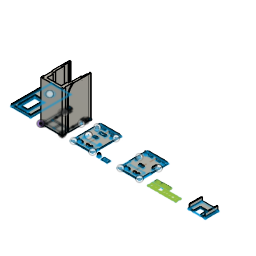
no_DICE-Enclosure-v18 (Autodesk Fusion 360 design; units mm, degrees)
part number: 2026-08-05-22-37-30-025
Autodesk Fusion 360 part; units mm, degrees
(part 1 of 2)
sketch "Frame" plane through (0, 0, 0) normal (0, 1, 0) x (1, 0, 0)
  line L0 (0, 0) -> (4, 0)
  line L1 (4, 0) -> (4, 42)
  line L2 (4, 42) -> (0, 42)
  line L3 (0, 42) -> (0, 0)
  line L4 (4, 39) -> (4, 42)
  line L5 (0, 0) -> (32, 0)
  line L6 (32, 0) -> (32, 3.8)
  line L7 (32, 3.8) -> (0, 3.8)
  line L8 (0, 3.8) -> (0, 0)
  line L9 (4, 13) -> (28, 13)
  line L10 (28, 13) -> (28, 15)
  line L11 (28, 15) -> (4, 15)
  line L12 (4, 15) -> (4, 13)
  line L13 (4, 18) -> (3.2, 18)
  line L14 (3.2, 18) -> (3.2, 20)
  line L15 (3.2, 20) -> (4, 20)
  line L16 (4, 20) -> (4, 18)
  line L17 (4, 39) -> (7, 39)
  line L18 (7, 39) -> (7, 35)
  line L19 (7, 35) -> (4, 35)
  line L20 (4, 35) -> (4, 39)
  line L21 (4, 42) -> (1, 42)
  line L22 (1, 42) -> (1, 39)
  line L23 (1, 39) -> (4, 39)
  line L24 (4, 39) -> (4, 42)
  line L25 (4, 3.8) -> (5.5, 3.8)
  line L26 (5.5, 3.8) -> (5.5, 13)
  line L27 (5.5, 13) -> (4, 13)
  line L28 (4, 13) -> (4, 3.8)
  line L29 (3.2, 20) -> (4, 20)
  line L30 (4, 20) -> (4, 35)
  line L31 (4, 35) -> (3.2, 35)
  line L32 (3.2, 35) -> (3.2, 20)
  line L33 (32, 0) -> (28, 0)
  line L34 (28, 0) -> (28, 42)
  line L35 (28, 42) -> (32, 42)
  line L36 (32, 42) -> (32, 0)
  line L37 (28, 18) -> (28.8, 18)
  line L38 (28.8, 18) -> (28.8, 20)
  line L39 (28.8, 20) -> (28, 20)
  line L40 (28, 20) -> (28, 18)
  line L41 (28, 39) -> (31, 39)
  line L42 (31, 39) -> (31, 42)
  line L43 (31, 42) -> (28, 42)
  line L44 (28, 42) -> (28, 39)
  line L45 (28, 39) -> (25, 39)
  line L46 (25, 39) -> (25, 35)
  line L47 (25, 35) -> (28, 35)
  line L48 (28, 35) -> (28, 39)
  line L49 (28.8, 20) -> (28, 20)
  line L50 (28, 20) -> (28, 35)
  line L51 (28, 35) -> (28.8, 35)
  line L52 (28.8, 35) -> (28.8, 20)
  line L53 (28, 3.8) -> (26.5, 3.8)
  line L54 (26.5, 3.8) -> (26.5, 13)
  line L55 (26.5, 13) -> (28, 13)
  line L56 (28, 13) -> (28, 3.8)
  line L57 (7, 36) -> (2, 36)
  line L58 (2, 36) -> (2, 37.4)
  line L59 (2, 37.4) -> (7, 37.4)
  line L60 (7, 37.4) -> (7, 36)
  line L61 (25, 36) -> (30, 36)
  line L62 (30, 36) -> (30, 37.4)
  line L63 (30, 37.4) -> (25, 37.4)
  line L64 (25, 37.4) -> (25, 36)
  line L65 (15, 13) -> (17, 13)
  line L66 (17, 13) -> (17, 3.8)
  line L67 (17, 3.8) -> (15, 3.8)
  line L68 (15, 3.8) -> (15, 13)
  line L69 (2, 37.4) -> (2, 39)
  line L70 (30, 37.4) -> (30, 39)
  line L71 (2, 36) -> (2, 32)
  line L72 (2, 32) -> (4, 32)
  line L73 (30, 36) -> (30, 32)
  line L74 (30, 32) -> (28, 32)
  line L75 (0, 42) -> (1, 42)
  line L76 (1, 42) -> (1, 42.1)
  line L77 (1, 42.1) -> (0, 42.1)
  line L78 (0, 42.1) -> (0, 42)
  line L79 (0, 42.1) -> (2, 42.1)
  line L80 (2, 42.1) -> (2, 43.1)
  line L81 (2, 43.1) -> (0, 43.1)
  line L82 (0, 43.1) -> (0, 42.1)
  line L83 (32, 42) -> (31, 42)
  line L84 (31, 42) -> (31, 42.1)
  line L85 (31, 42.1) -> (32, 42.1)
  line L86 (32, 42.1) -> (32, 42)
  line L87 (32, 42.1) -> (30, 42.1)
  line L88 (30, 42.1) -> (30, 43.1)
  line L89 (30, 43.1) -> (32, 43.1)
  line L90 (32, 43.1) -> (32, 42.1)
  circle A0 centre (1.6, 30) radius 0.65
  circle A1 centre (30.4, 30) radius 0.65
  circle A2 centre (2, 2) radius 0.65
  circle A3 centre (30, 2) radius 0.65
  circle A4 centre (2, 37) radius 0.65
  circle A5 centre (30, 37) radius 0.65
  dimension "d1" = 4
  dimension "d2" = 42
  dimension "d4" = 32
  dimension "d5" = 3.8
  dimension "d6" = 24
  dimension "d7" = 2
  dimension "d8" = 0.8
  dimension "d9" = 2
  dimension "d10" = 3
  dimension "d11" = 4
  dimension "d12" = 9.2
  dimension "d13" = 3
  dimension "d14" = 3
  dimension "d15" = 3
  dimension "d16" = 1.5
  dimension "d17" = 4
  dimension "d18" = 42
  dimension "d19" = 0.8
  dimension "d20" = 2
  dimension "d21" = 3
  dimension "d22" = 3
  dimension "d23" = 3
  dimension "d24" = 3
  dimension "d25" = 4
  dimension "d26" = 1.5
  dimension "d27" = 9.2
  dimension "d43" = 3
  dimension "d44" = 5
  dimension "d45" = 1.4
  dimension "d46" = 5
  dimension "d47" = 1.4
  dimension "d52" = 1
  dimension "d53" = 1
  dimension "d133" = 2
  dimension "d134" = 15
  dimension "d164" = 4
  dimension "d165" = 4
  dimension "d174" = 0.1
  dimension "d175" = 2
  dimension "d176" = 1
  dimension "d177" = 0.1
  dimension "d178" = 2
  dimension "d179" = 1
  dimension "d428" = 1.3
  dimension "d429" = 1.6
  dimension "d430" = 2
  dimension "d431" = 1.3
  dimension "d432" = 1.6
  dimension "d433" = 2
  dimension "d434" = 1.3
  dimension "d435" = 2
  dimension "d436" = 2
  dimension "d437" = 1.3
  dimension "d438" = 2
  dimension "d439" = 2
  dimension "d458" = 1.3
  dimension "d459" = 2
  dimension "d460" = 6.1
  dimension "d461" = 1.3
  dimension "d462" = 2
  dimension "d463" = 6.1
  constraint horizontal L0
  constraint vertical L1
  constraint horizontal L2
  constraint vertical L3
  constraint coincident L0.start L3.end
  constraint vertical L4
  constraint horizontal L5
  constraint vertical L6
  constraint horizontal L7
  constraint vertical L8
  constraint horizontal L9
  constraint vertical L10
  constraint horizontal L11
  constraint vertical L12
  constraint coincident L1 L9.start
  constraint horizontal L13
  constraint vertical L14
  constraint horizontal L15
  constraint vertical L16
  constraint coincident L1 L13.start
  constraint horizontal L17
  constraint vertical L18
  constraint horizontal L19
  constraint vertical L20
  constraint horizontal L21
  constraint vertical L22
  constraint horizontal L23
  constraint vertical L24
  constraint horizontal L25
  constraint vertical L26
  constraint horizontal L27
  constraint vertical L28
  constraint coincident L7 L25.start
  constraint coincident L1 L25.start
  constraint horizontal L29
  constraint vertical L30
  constraint horizontal L31
  constraint vertical L32
  constraint horizontal L33
  constraint vertical L34
  constraint horizontal L35
  constraint vertical L36
  constraint horizontal L37
  constraint vertical L38
  constraint horizontal L39
  constraint vertical L40
  constraint coincident L34 L37.start
  constraint horizontal L41
  constraint vertical L42
  constraint horizontal L43
  constraint vertical L44
  constraint coincident L34 L41.start
  constraint horizontal L45
  constraint vertical L46
  constraint horizontal L47
  constraint vertical L48
  constraint horizontal L49
  constraint vertical L50
  constraint horizontal L51
  constraint vertical L52
  constraint horizontal L53
  constraint vertical L54
  constraint horizontal L55
  constraint vertical L56
  constraint coincident L7 L53.start
  constraint coincident L34 L53.start
  constraint collinear L35 L43
  constraint horizontal L57
  constraint vertical L58
  constraint horizontal L59
  constraint vertical L60
  constraint coincident L18 L57.start
  constraint horizontal L61
  constraint vertical L62
  constraint horizontal L63
  constraint vertical L64
  constraint coincident L46 L61.start
  constraint horizontal L65
  constraint vertical L66
  constraint horizontal L67
  constraint vertical L68
  constraint coincident L9 L65.start
  constraint coincident L23 L69.end
  constraint perpendicular L23 L69
  constraint coincident L41 L70.end
  constraint perpendicular L41 L70
  constraint perpendicular L57 L71
  constraint perpendicular L32 L72
  constraint perpendicular L61 L73
  constraint coincident L50 L74.end
  constraint horizontal L75
  constraint vertical L76
  constraint horizontal L77
  constraint vertical L78
  constraint horizontal L79
  constraint vertical L80
  constraint horizontal L81
  constraint vertical L82
  constraint horizontal L83
  constraint vertical L84
  constraint horizontal L85
  constraint vertical L86
  constraint horizontal L87
  constraint vertical L88
  constraint horizontal L89
  constraint vertical L90
  measures "d1" distance of L0.start L0.end
  measures "d2" distance of L0.start L2.end
  measures "d4" distance of L0.start L5.end
  measures "d5" distance of L0.start L7.end
  measures "d6" distance of L9.start L9.end
  measures "d7" distance of L9.start L11.end
  measures "d8" distance of L13.start L13.end
  measures "d9" distance of L13.start L15.end
  measures "d10" distance of L4.start L17.end
  measures "d11" distance of L4.start L19.end
  measures "d12" distance of L7 L9
  measures "d13" distance of L11 L13
  measures "d14" distance of L1.end L21.end
  measures "d15" distance of L1.end L4.start
  measures "d16" distance of L25.start L25.end
  measures "d17" distance of L5.end L33.end
  measures "d18" distance of L5.end L35.end
  measures "d19" distance of L37.start L37.end
  measures "d20" distance of L37.start L39.end
  measures "d21" distance of L11 L37
  measures "d22" distance of L41.start L41.end
  measures "d23" distance of L41.start L34.end
  measures "d24" distance of L41.start L45.end
  measures "d25" distance of L41.start L47.end
  measures "d26" distance of L53.start L53.end
  measures "d27" distance of L53.start L9.end
  measures "d43" distance of L2 L17
  measures "d44" distance of L57.start L57.end
  measures "d45" distance of L57.start L59.end
  measures "d46" distance of L61.start L61.end
  measures "d47" distance of L61.start L63.end
  measures "d52" distance of L19 L57
  measures "d53" distance of L47 L61
  measures "d133" distance of L65.start L65.end
  measures "d134" distance of L3 L68
  measures "d164" distance of L57.end L71.end
  measures "d165" distance of L61.end L73.end
  measures "d174" distance of L2.end L77.end
  measures "d175" distance of L77.end L79.end
  measures "d176" distance of L77.end L81.end
  measures "d177" distance of L35.end L85.end
  measures "d178" distance of L85.end L87.end
  measures "d179" distance of L85.end L89.end
  measures "d428" diameter of A0
  measures "d429" distance of L3 A0.centre
  measures "d430" distance of L72 A0.centre
  measures "d431" diameter of A1
  measures "d432" distance of L36 A1.centre
  measures "d433" distance of L74 A1.centre
  measures "d434" diameter of A2
  measures "d435" distance of L0 A2.centre
  measures "d436" distance of L3 A2.centre
  measures "d437" diameter of A3
  measures "d438" distance of L5 A3.centre
  measures "d439" distance of L6 A3.centre
  measures "d458" diameter of A4
  measures "d459" distance of L3 A4.centre
  measures "d460" distance of L81 A4.centre
  measures "d461" diameter of A5
  measures "d462" distance of L36 A5.centre
  measures "d463" distance of L89 A5.centre
extrude "Extrude4" add sketch "Frame" along normal blind 10 contours L0 L1 L3 L5 L7 L8 | L1 L5 L7 L25 L34 L53 L67 | L1 L2 L3 L7 L12 L13 L14 L22 L23 L28 L32 L58 L69 L71 L72 L75 A4 | L1 L7 L9 L25 L26 L27 L28 | L5 L6 L7 L33 L34 L36 | L7 L10 L34 L35 L36 L37 L38 L41 L42 L52 L56 L62 L70 L73 L74 L83 A5 | L7 L9 L34 L53 L54 L55 L56 | L1 L20 L23 L59 L69 A4 | L1 L20 L57 L58 L59 A4 | L59 L69 A4 | L58 L69 A4 | L1 L20 L31 L32 L57 L71 L72 | L58 L59 A4 | L34 L41 L48 L63 L70 A5 | L34 L48 L51 L52 L61 L73 L74 | L34 L48 L61 L62 L63 A5 | L62 L70 A5 | L63 L70 A5 | L62 L63 A5 | A0 | A1 | A2 | A3 makes body 1
extrude "Extrude5" add sketch "Frame" along normal blind 10 contours L1 L15 L29 L30 L32 L72 | L1 L30 L31 L32 L72 | L34 L39 L49 L50 L52 L74 | L34 L50 L51 L52 L74 bodies 1
extrude "Extrude6" add sketch "Frame" along normal blind 10 contours L1 L9 L10 L11 L12 L27 L34 L55 L65 bodies 1
extrude "Extrude7" add sketch "Frame" along normal blind 10 contours L1 L17 L18 L20 L59 | L1 L18 L20 L57 L59 L60 | L1 L18 L19 L20 L57 | L34 L45 L46 L48 L63 | L34 L46 L47 L48 L61 | L34 L46 L48 L61 L63 L64 bodies 1
extrude "Extrude8" cut sketch "Frame" along normal blind 10 contours L1 L18 L20 L57 L59 L60 | L1 L20 L57 L58 L59 A4 | L58 L59 A4 | L34 L48 L61 L62 L63 A5 | L34 L46 L48 L61 L63 L64 | L62 L63 A5 bodies 1
extrude "Extrude9" add sketch "Frame" along normal blind 5 contours L1 L18 L20 L57 L59 L60 | L1 L20 L57 L58 L59 A4 | L58 L59 A4 | L34 L48 L61 L62 L63 A5 | L34 L46 L48 L61 L63 L64 | L62 L63 A5 bodies 1
sketch "Side IO" plane through (0, 0, 0) normal (0, 1, 0) x (1, 0, 0)
  line L0 (45, 0.0196) -> (77, 0.0196)
  line L1 (77, 0.0196) -> (77, 43.1196)
  line L2 (77, 43.1196) -> (45, 43.1196)
  line L3 (45, 43.1196) -> (45, 0.0196)
  circle A0 centre (47, 2.0196) radius 1.1
  circle A1 centre (75, 2.0196) radius 1.1
  circle A2 centre (47, 37.0196) radius 1.1
  circle A3 centre (75, 37.0196) radius 1.1
  line L4 (50.6, 4.0196) -> (71.4, 4.0196)
  line L5 (71.4, 4.0196) -> (71.4, 13.0196)
  line L6 (71.4, 13.0196) -> (50.6, 13.0196)
  line L7 (50.6, 13.0196) -> (50.6, 4.0196)
  line L8 (49.1, 15.0196) -> (51.1, 15.0196)
  line L9 (51.1, 15.0196) -> (51.1, 17.0196)
  line L10 (51.1, 17.0196) -> (49.1, 17.0196)
  line L11 (49.1, 17.0196) -> (49.1, 15.0196)
  line L12 (51.1, 17.0196) -> (50.1, 17.0196)
  line L13 (50.1, 17.0196) -> (50.1, 16.0196)
  line L14 (50.1, 16.0196) -> (51.1, 16.0196)
  line L15 (51.1, 16.0196) -> (51.1, 17.0196)
  line L16 (72.9, 15.0196) -> (70.9, 15.0196)
  line L17 (70.9, 15.0196) -> (70.9, 17.0196)
  line L18 (70.9, 17.0196) -> (72.9, 17.0196)
  line L19 (72.9, 17.0196) -> (72.9, 15.0196)
  line L20 (70.9, 17.0196) -> (71.9, 17.0196)
  line L21 (71.9, 17.0196) -> (71.9, 16.0196)
  line L22 (71.9, 16.0196) -> (70.9, 16.0196)
  line L23 (70.9, 16.0196) -> (70.9, 17.0196)
  line L24 (49.1, 34.7196) -> (51.1, 34.7196)
  line L25 (51.1, 34.7196) -> (51.1, 32.7196)
  line L26 (51.1, 32.7196) -> (49.1, 32.7196)
  line L27 (49.1, 32.7196) -> (49.1, 34.7196)
  line L28 (51.1, 32.7196) -> (50.1, 32.7196)
  line L29 (50.1, 32.7196) -> (50.1, 33.7196)
  line L30 (50.1, 33.7196) -> (51.1, 33.7196)
  line L31 (51.1, 33.7196) -> (51.1, 32.7196)
  line L32 (70.9, 32.7196) -> (72.9, 32.7196)
  line L33 (72.9, 32.7196) -> (72.9, 34.7196)
  line L34 (72.9, 34.7196) -> (70.9, 34.7196)
  line L35 (70.9, 34.7196) -> (70.9, 32.7196)
  line L36 (70.9, 32.7196) -> (71.9, 32.7196)
  line L37 (71.9, 32.7196) -> (71.9, 33.7196)
  line L38 (71.9, 33.7196) -> (70.9, 33.7196)
  line L39 (70.9, 33.7196) -> (70.9, 32.7196)
  line L40 (56.5, 23.8196) -> (62.5, 23.8196)
  line L41 (62.5, 23.8196) -> (62.5, 20.6196)
  line L42 (62.5, 20.6196) -> (56.5, 20.6196)
  line L43 (56.5, 20.6196) -> (56.5, 23.8196)
  line L44 (56.2, 33.2196) -> (65.8, 33.2196)
  line L45 (65.8, 33.2196) -> (65.8, 29.8196)
  line L46 (65.8, 29.8196) -> (56.2, 29.8196)
  line L47 (56.2, 29.8196) -> (56.2, 33.2196)
  line L48 (50.6, 4.0196) -> (52.6, 4.0196)
  line L49 (52.6, 4.0196) -> (52.6, 6.0196)
  line L50 (52.6, 6.0196) -> (50.6, 6.0196)
  line L51 (50.6, 6.0196) -> (50.6, 4.0196)
  line L52 (52.6, 6.0196) -> (51.6, 6.0196)
  line L53 (51.6, 6.0196) -> (51.6, 5.0196)
  line L54 (51.6, 5.0196) -> (52.6, 5.0196)
  line L55 (52.6, 5.0196) -> (52.6, 6.0196)
  line L56 (71.4, 4.0196) -> (69.4, 4.0196)
  line L57 (69.4, 4.0196) -> (69.4, 6.0196)
  line L58 (69.4, 6.0196) -> (71.4, 6.0196)
  line L59 (71.4, 6.0196) -> (71.4, 4.0196)
  line L60 (69.4, 6.0196) -> (70.4, 6.0196)
  line L61 (70.4, 6.0196) -> (70.4, 5.0196)
  line L62 (70.4, 5.0196) -> (69.4, 5.0196)
  line L63 (69.4, 5.0196) -> (69.4, 6.0196)
  line L64 (54, 4.0196) -> (58, 4.0196)
  line L65 (58, 4.0196) -> (58, 5.0196)
  line L66 (58, 5.0196) -> (54, 5.0196)
  line L67 (54, 5.0196) -> (54, 4.0196)
  line L68 (61, 4.0196) -> (61, 13.0196) construction
  line L69 (64, 4.0196) -> (68, 4.0196)
  line L70 (68, 4.0196) -> (68, 5.0196)
  line L71 (68, 5.0196) -> (64, 5.0196)
  line L72 (64, 5.0196) -> (64, 4.0196)
  line L73 (46.8, 43.1196) -> (75.2, 43.1196)
  line L74 (75.2, 43.1196) -> (75.2, 42.1196)
  line L75 (75.2, 42.1196) -> (46.8, 42.1196)
  line L76 (46.8, 42.1196) -> (46.8, 43.1196)
  line L77 (61, 13.0196) -> (61, 42.1196) construction
  line L78 (58, 39.1196) -> (52, 39.1196)
  line L79 (52, 39.1196) -> (52, 38.1196)
  line L80 (52, 38.1196) -> (58, 38.1196)
  line L81 (58, 38.1196) -> (58, 39.1196)
  line L82 (64, 39.1196) -> (70, 39.1196)
  line L83 (70, 39.1196) -> (70, 38.1196)
  line L84 (70, 38.1196) -> (64, 38.1196)
  line L85 (64, 38.1196) -> (64, 39.1196)
  line L86 (45, 5.0196) -> (46, 5.0196)
  line L87 (46, 5.0196) -> (46, 9.0196)
  line L88 (46, 9.0196) -> (45, 9.0196)
  line L89 (45, 9.0196) -> (45, 5.0196)
  line L90 (77, 5.0196) -> (76, 5.0196)
  line L91 (76, 5.0196) -> (76, 9.0196)
  line L92 (76, 9.0196) -> (77, 9.0196)
  line L93 (77, 9.0196) -> (77, 5.0196)
  circle A4 centre (50.8, 20.2196) radius 0.4
  dimension "d54" = 32
  dimension "d55" = 43.1
  dimension "d56" = 2.2
  dimension "d57" = 2
  dimension "d58" = 2
  dimension "d59" = 2.2
  dimension "d60" = 2
  dimension "d61" = 2
  dimension "d62" = 2.2
  dimension "d63" = 6.1
  dimension "d64" = 2
  dimension "d65" = 2.2
  dimension "d66" = 6.1
  dimension "d67" = 2
  dimension "d68" = 20.8
  dimension "d69" = 9
  dimension "d70" = 4
  dimension "d71" = 5.6
  dimension "d73" = 2
  dimension "d74" = 2
  dimension "d75" = 4.1
  dimension "d76" = 2
  dimension "d77" = 2
  dimension "d78" = 2
  dimension "d79" = 2
  dimension "d80" = 4.1
  dimension "d81" = 2
  dimension "d82" = 2
  dimension "d83" = 4.1
  dimension "d84" = 8.4
  dimension "d85" = 2
  dimension "d86" = 2
  dimension "d87" = 4.1
  dimension "d88" = 8.4
  dimension "d89" = 6
  dimension "d90" = 3.2
  dimension "d91" = 20.6
  dimension "d93" = 11.5
  dimension "d94" = 9.6
  dimension "d95" = 3.4
  dimension "d96" = 11.2
  dimension "d109" = 2
  dimension "d110" = 2
  dimension "d111" = 1
  dimension "d112" = 1
  dimension "d113" = 2
  dimension "d114" = 2
  dimension "d115" = 1
  dimension "d116" = 1
  dimension "d121" = 1
  dimension "d122" = 1
  dimension "d123" = 1
  dimension "d124" = 1
  dimension "d125" = 1
  dimension "d126" = 1
  dimension "d127" = 1
  dimension "d128" = 1
  dimension "d182" = 4
  dimension "d183" = 1
  dimension "d184" = 3
  dimension "d185" = 4
  dimension "d186" = 1
  dimension "d187" = 3
  dimension "d192" = 29.8
  dimension "d193" = 28.4
  dimension "d194" = 1
  dimension "d195" = 1.8
  dimension "d345" = 6
  dimension "d346" = 1
  dimension "d347" = 3
  dimension "d348" = 4
  dimension "d349" = 6
  dimension "d350" = 1
  dimension "d351" = 3
  dimension "d352" = 4
  dimension "d372" = 1
  dimension "d373" = 4
  dimension "d374" = 5
  dimension "d375" = 1
  dimension "d376" = 4
  dimension "d377" = 5
  dimension "d423" = 0.8
  dimension "d424" = 20.2
  dimension "d425" = 5.8
  constraint horizontal L0
  constraint vertical L1
  constraint horizontal L2
  constraint vertical L3
  constraint horizontal L4
  constraint vertical L5
  constraint horizontal L6
  constraint vertical L7
  constraint horizontal L8
  constraint vertical L9
  constraint horizontal L10
  constraint vertical L11
  constraint horizontal L12
  constraint vertical L13
  constraint horizontal L14
  constraint vertical L15
  constraint horizontal L16
  constraint vertical L17
  constraint horizontal L18
  constraint vertical L19
  constraint horizontal L20
  constraint vertical L21
  constraint horizontal L22
  constraint vertical L23
  constraint horizontal L24
  constraint vertical L25
  constraint horizontal L26
  constraint vertical L27
  constraint horizontal L28
  constraint vertical L29
  constraint horizontal L30
  constraint vertical L31
  constraint horizontal L32
  constraint vertical L33
  constraint horizontal L34
  constraint vertical L35
  constraint horizontal L36
  constraint vertical L37
  constraint horizontal L38
  constraint vertical L39
  constraint horizontal L40
  constraint vertical L41
  constraint horizontal L42
  constraint vertical L43
  constraint horizontal L44
  constraint vertical L45
  constraint horizontal L46
  constraint vertical L47
  constraint horizontal L48
  constraint vertical L49
  constraint horizontal L50
  constraint vertical L51
  constraint horizontal L52
  constraint vertical L53
  constraint horizontal L54
  constraint vertical L55
  constraint horizontal L56
  constraint vertical L57
  constraint horizontal L58
  constraint vertical L59
  constraint horizontal L60
  constraint vertical L61
  constraint horizontal L62
  constraint vertical L63
  constraint horizontal L64
  constraint vertical L65
  constraint horizontal L66
  constraint vertical L67
  constraint coincident L4 L64.start
  constraint midpoint L4 L68.start
  constraint midpoint L6 L68.end
  constraint horizontal L69
  constraint vertical L70
  constraint horizontal L71
  constraint vertical L72
  constraint coincident L4 L69.start
  constraint horizontal L73
  constraint vertical L74
  constraint horizontal L75
  constraint vertical L76
  constraint coincident L2 L73.start
  constraint midpoint L75 L77.end
  constraint horizontal L78
  constraint vertical L79
  constraint horizontal L80
  constraint vertical L81
  constraint horizontal L82
  constraint vertical L83
  constraint horizontal L84
  constraint vertical L85
  constraint horizontal L86
  constraint vertical L87
  constraint horizontal L88
  constraint vertical L89
  constraint coincident L3 L86.start
  constraint horizontal L90
  constraint vertical L91
  constraint horizontal L92
  constraint vertical L93
  constraint coincident L1 L90.start
  measures "d54" distance of L0.start L0.end
  measures "d55" distance of L0.start L2.end
  measures "d56" diameter of A0
  measures "d57" distance of L0 A0.centre
  measures "d58" distance of L3 A0.centre
  measures "d59" diameter of A1
  measures "d60" distance of L0 A1.centre
  measures "d61" distance of L1 A1.centre
  measures "d62" diameter of A2
  measures "d63" distance of L2 A2.centre
  measures "d64" distance of L3 A2.centre
  measures "d65" diameter of A3
  measures "d66" distance of L2 A3.centre
  measures "d67" distance of L1 A3.centre
  measures "d68" distance of L4.start L4.end
  measures "d69" distance of L4.start L6.end
  measures "d70" distance of L0 L4
  measures "d71" distance of L3 L7
  measures "d73" distance of L8.start L8.end
  measures "d74" distance of L8.start L10.end
  measures "d75" distance of L3 L11
  measures "d76" distance of L6 L8
  measures "d77" distance of L16.start L16.end
  measures "d78" distance of L16.start L18.end
  measures "d79" distance of L6 L16
  measures "d80" distance of L1 L19
  measures "d81" distance of L24.start L24.end
  measures "d82" distance of L24.start L26.end
  measures "d83" distance of L3 L27
  measures "d84" distance of L2 L24
  measures "d85" distance of L32.start L32.end
  measures "d86" distance of L32.start L34.end
  measures "d87" distance of L1 L33
  measures "d88" distance of L2 L34
  measures "d89" distance of L40.start L40.end
  measures "d90" distance of L40.start L42.end
  measures "d91" distance of L0 L42
  measures "d93" distance of L3 L43
  measures "d94" distance of L44.start L44.end
  measures "d95" distance of L44.start L46.end
  measures "d96" distance of L3 L47
  measures "d109" distance of L4.start L48.end
  measures "d110" distance of L4.start L50.end
  measures "d111" distance of L49.end L52.end
  measures "d112" distance of L49.end L54.end
  measures "d113" distance of L4.end L56.end
  measures "d114" distance of L4.end L58.end
  measures "d115" distance of L57.end L60.end
  measures "d116" distance of L57.end L62.end
  measures "d121" distance of L11 L13
  measures "d122" distance of L8 L14
  measures "d123" distance of L16 L22
  measures "d124" distance of L19 L21
  measures "d125" distance of L34 L38
  measures "d126" distance of L33 L37
  measures "d127" distance of L24 L30
  measures "d128" distance of L27 L29
  measures "d182" distance of L64.start L64.end
  measures "d183" distance of L64.start L66.end
  measures "d184" distance of L65 L68
  measures "d185" distance of L69.start L69.end
  measures "d186" distance of L69.start L71.end
  measures "d187" distance of L68 L72
  measures "d192" distance of L0 L46
  measures "d193" distance of L73.start L73.end
  measures "d194" distance of L73.start L75.end
  measures "d195" distance of L3 L76
  measures "d345" distance of L78.start L78.end
  measures "d346" distance of L78.start L80.end
  measures "d347" distance of L77 L81
  measures "d348" distance of L2 L78
  measures "d349" distance of L82.start L82.end
  measures "d350" distance of L82.start L84.end
  measures "d351" distance of L77 L85
  measures "d352" distance of L2 L82
  measures "d372" distance of L86.start L86.end
  measures "d373" distance of L86.start L88.end
  measures "d374" distance of L0 L86
  measures "d375" distance of L90.start L90.end
  measures "d376" distance of L90.start L92.end
  measures "d377" distance of L0 L90
  measures "d423" diameter of A4
  measures "d424" distance of L0 A4.centre
  measures "d425" distance of L3 A4.centre
extrude "Extrude10" add sketch "Side IO" along normal blind 1 separate body contours L0 L1 L2 L3 L74 L75 L76 L86 L87 L88 L90 L91 L92 | L3 L86 L87 L88 L89 | L1 L90 L91 L92 L93 | L2 L73 L74 L75 L76 | L9 L10 L12 L13 L14 L15 | L17 L18 L20 L21 L22 L23 | L25 L26 L28 L29 L30 L31 | L32 L35 L36 L37 L38 L39 | L78 L79 L80 L81 | L82 L83 L84 L85 | A4 makes body 2
extrude "Extrude11" add sketch "Side IO" along normal blind 1 contours L4 L7 L48 L49 L50 L51 L53 L54 | L4 L5 L6 L7 L49 L50 L52 L55 L57 L58 L60 L63 L65 L66 L67 L70 L71 L72 | L4 L64 L65 L66 L67 | L49 L50 L52 L53 L54 L55 | L4 L69 L70 L71 L72 | L4 L5 L56 L57 L58 L59 L61 L62 | L57 L58 L60 L61 L62 L63 | L8 L9 L10 L11 L13 L14 | L16 L17 L18 L19 L21 L22 | L24 L25 L26 L27 L29 L30 | L32 L33 L34 L35 L37 L38 bodies 2
sketch "Switch Handle (exp)" plane through (0, 0, 0) normal (0, 1, 0) x (1, 0, 0)
  line L0 (85, 0) -> (86.9, 0)
  line L1 (86.9, 0) -> (86.9, 1.9)
  line L2 (86.9, 1.9) -> (85, 1.9)
  line L3 (85, 1.9) -> (85, 0)
  line L4 (84.6, -0.4) -> (87.3, -0.4)
  line L5 (87.3, -0.4) -> (87.3, 2.3)
  line L6 (87.3, 2.3) -> (84.6, 2.3)
  line L7 (84.6, 2.3) -> (84.6, -0.4)
  dimension "d102" = 1.9
  dimension "d103" = 1.9
  dimension "d104" = 0.4
  constraint horizontal L0
  constraint vertical L1
  constraint horizontal L2
  constraint vertical L3
  measures "d102" distance of L0.start L0.end
  measures "d103" distance of L0.start L2.end
extrude "Extrude12" add sketch "Switch Handle (exp)" along normal blind 4 separate body makes body 3
extrude "Extrude13" add sketch "Switch Handle (exp)" along normal blind 1 contours L0 L1 L2 L3 bodies 3
extrude "Extrude14" add sketch "Side IO" along normal blind 4 contours L4 L7 L48 L49 L50 L51 L53 L54 | L4 L5 L56 L57 L58 L59 L61 L62 | L24 L25 L26 L27 L29 L30 | L32 L33 L34 L35 L37 L38 bodies 2
fillet "Fillet1" radius 1 4 edges at (56.2, 0.5, -33.2196) (65.8, 0.5, -33.2196) (65.8, 0.5, -29.8196) (56.2, 0.5, -29.8196) on bodies 2
fillet "Fillet2" radius 1 4 edges at (56.5, 0.5, -23.8196) (62.5, 0.5, -23.8196) (62.5, 0.5, -20.6196) (56.5, 0.5, -20.6196) on bodies 2
extrude "Extrude15" add sketch "Frame" along normal blind 0.6 contours L1 L13 L14 L15 L16 L29 | L34 L37 L38 L39 L40 L49 bodies 1
extrude "Extrude16" add sketch "Frame" along normal blind 1 contours L7 L9 L65 L66 L67 L68 bodies 1
sketch "Top" plane through (0, 0, 0) normal (0, 1, 0) x (1, 0, 0)
  line L0 (-15, 0) -> (-44.2, 0)
  line L1 (-44.2, 0) -> (-44.2, 59.8)
  line L2 (-44.2, 59.8) -> (-15, 59.8)
  line L3 (-15, 59.8) -> (-15, 0)
  line L4 (-25, 5.8) -> (-37.8, 5.8)
  line L5 (-37.8, 5.8) -> (-37.8, 29)
  line L6 (-37.8, 29) -> (-25, 29)
  line L7 (-25, 29) -> (-25, 5.8)
  circle A0 centre (-31.4, 44.8) radius 3.6
  line L8 (-16, 58.8) -> (-16, 1)
  line L9 (-16, 1) -> (-43.2, 1)
  line L10 (-43.2, 1) -> (-43.2, 58.8)
  line L11 (-43.2, 58.8) -> (-16, 58.8)
  line L12 (-25.4, 6.2) -> (-37.4, 6.2)
  line L13 (-37.4, 6.2) -> (-37.4, 28.6)
  line L14 (-37.4, 28.6) -> (-25.4, 28.6)
  line L15 (-25.4, 28.6) -> (-25.4, 6.2)
  circle A1 centre (-31.4, 44.8) radius 5.6
  line L16 (-24, 30) -> (-24, 4.8)
  line L17 (-24, 4.8) -> (-38.8, 4.8)
  line L18 (-38.8, 4.8) -> (-38.8, 30)
  line L19 (-38.8, 30) -> (-24, 30)
  dimension "d137" = 29.2
  dimension "d138" = 59.8
  dimension "d139" = 12.8
  dimension "d140" = 23.2
  dimension "d141" = 5.8
  dimension "d143" = 7.2
  dimension "d144" = 12.8
  dimension "d145" = 15
  dimension "d146" = 1
  dimension "d147" = 0.4
  dimension "d148" = 2
  dimension "d151" = -1
  dimension "d358" = 6.4
  constraint horizontal L0
  constraint vertical L1
  constraint horizontal L2
  constraint vertical L3
  constraint horizontal L4
  constraint vertical L5
  constraint horizontal L6
  constraint vertical L7
  measures "d137" distance of L0.start L0.end
  measures "d138" distance of L0.start L2.end
  measures "d139" distance of L4.start L4.end
  measures "d140" distance of L4.start L6.end
  measures "d141" distance of L0 L4
  measures "d143" diameter of A0
  measures "d144" distance of L1 A0.centre
  measures "d145" distance of L2 A0.centre
  measures "d358" distance of L1 L5
extrude "Extrude19" add sketch "Top" along normal blind 1 separate body contours L0 L1 L2 L3 | L8 L9 L10 L11 | A1 | L16 L17 L18 L19 makes body 4
extrude "Extrude20" add sketch "Top" along normal blind 3 contours L0 L1 L2 L3 | A1 | L16 L17 L18 L19 bodies 4
extrude "Extrude21" add sketch "Top" along normal blind 0.8 contours L4 L5 L6 L7 bodies 4
fillet "Fillet3" radius 1 4 edges at (-16, 2, -58.8) (-16, 2, -1) (-43.2, 2, -1) (-43.2, 2, -58.8) on bodies 4
extrude "Extrude23" add sketch "Frame" along normal blind 22 contours L0 L1 L3 L5 L7 L8 | L1 L5 L7 L25 L34 L53 L67 | L1 L2 L3 L7 L12 L13 L14 L22 L23 L28 L32 L58 L69 L71 L72 L75 A4 | L1 L7 L9 L25 L26 L27 L28 | L5 L6 L7 L33 L34 L36 | L1 L9 L10 L11 L12 L27 L34 L55 L65 | L7 L10 L34 L35 L36 L37 L38 L41 L42 L52 L56 L62 L70 L73 L74 L83 A5 | L7 L9 L34 L53 L54 L55 L56 | L1 L15 L29 L30 L32 L72 | L58 L69 A4 | L34 L39 L49 L50 L52 L74 | L62 L70 A5 | A0 | A1 | A2 | A3 bodies 1
extrude "Extrude25" add sketch "Frame" along normal blind 60 contours L0 L1 L3 L5 L7 L8 | L1 L5 L7 L25 L34 L53 L67 | L1 L2 L3 L7 L12 L13 L14 L22 L23 L28 L32 L58 L69 L71 L72 L75 A4 | L1 L7 L9 L25 L26 L27 L28 | L5 L6 L7 L33 L34 L36 | L7 L10 L34 L35 L36 L37 L38 L41 L42 L52 L56 L62 L70 L73 L74 L83 A5 | L7 L9 L34 L53 L54 L55 L56 | L58 L69 A4 | L62 L70 A5 | A0 | A1 | A2 | A3 bodies 1
extrude "Extrude26" add sketch "Frame" along normal blind 60 contours L2 L75 L76 L77 L78 L79 | L77 L79 L80 L81 L82 | L35 L83 L84 L85 L86 L87 | L85 L87 L88 L89 L90 bodies 1
extrude "Extrude27" add sketch "Side IO" along normal blind 4 contours L4 L64 L65 L66 L67 | L4 L69 L70 L71 L72 bodies 2
fillet "Fillet4" radius 0.4 2 edges at (56, 1, -5.0196) (66, 1, -5.0196) on bodies 2
extrude "Extrude28" add sketch "Side IO" along normal blind 2 contours L2 L73 L74 L75 L76 bodies 2
fillet "Fillet5" radius 0.4 4 edges at (77, 0.5, -0.0196) (45, 0.5, -0.0196) (77, 0.5, -43.1196) (45, 0.5, -43.1196) on bodies 2
sketch "Switch Skirt" plane through (0, 0, 0) normal (0, 1, 0) x (1, 0, 0)
  line L0 (95, 0) -> (96.9, 0)
  line L1 (96.9, 0) -> (96.9, 1.9)
  line L2 (96.9, 1.9) -> (95, 1.9)
  line L3 (95, 1.9) -> (95, 0)
  line L4 (91.65, 3.25) -> (100.25, 3.25)
  line L5 (100.25, 3.25) -> (100.25, -1.35)
  line L6 (100.25, -1.35) -> (91.65, -1.35)
  line L7 (91.65, -1.35) -> (91.65, 3.25)
  dimension "d202" = 1.9
  dimension "d203" = 1.9
  dimension "d204" = 8.6
  dimension "d205" = 4.6
  dimension "d206" = 3.35
  dimension "d207" = 1.35
  constraint horizontal L0
  constraint vertical L1
  constraint horizontal L2
  constraint vertical L3
  constraint horizontal L4
  constraint vertical L5
  constraint horizontal L6
  constraint vertical L7
  measures "d202" distance of L0.start L0.end
  measures "d203" distance of L0.start L2.end
  measures "d204" distance of L4.start L4.end
  measures "d205" distance of L4.start L6.end
  measures "d206" distance of L3 L7
  measures "d207" distance of L2 L4
extrude "Extrude29" add sketch "Switch Skirt" along normal blind 0.6 separate body makes body 5
sketch "Side" plane through (0, 0, 0) normal (0, 1, 0) x (1, 0, 0)
  line L0 (122.6, 3.8665) -> (122.6, 5.8665)
  line L1 (139.4, 4.8665) -> (139.4, 5.8665)
  line L2 (141.4, 3.8665) -> (141.4, 12.9665)
  line L3 (140.4, 4.8665) -> (139.4, 4.8665)
  circle A0 centre (145, 1.9665) radius 1.1
  line L4 (120.6, 12.9665) -> (120.6, 3.8665)
  line L5 (134, 4.8665) -> (134, 3.8665)
  line L6 (131, 3.8665) -> (131, 12.9665) construction
  line L7 (139.4, 5.8665) -> (141.4, 5.8665)
  line L8 (139.4, 3.8665) -> (139.4, 5.8665)
  line L9 (138, 3.8665) -> (138, 4.8665)
  line L10 (124, 3.8665) -> (128, 3.8665)
  line L11 (139.4, 5.8665) -> (140.4, 5.8665)
  circle A1 centre (117, 1.9665) radius 1.1
  line L12 (141.4, 3.8665) -> (139.4, 3.8665)
  line L13 (124, 4.8665) -> (124, 3.8665)
  line L14 (140.4, 5.8665) -> (140.4, 4.8665)
  line L15 (128, 4.8665) -> (124, 4.8665)
  line L16 (141.4, 5.8665) -> (141.4, 3.8665)
  line L17 (128, 3.8665) -> (128, 4.8665)
  line L18 (122.6, 4.8665) -> (122.6, 5.8665)
  line L19 (141.4, 12.9665) -> (120.6, 12.9665)
  line L20 (121.6, 5.8665) -> (121.6, 4.8665)
  line L21 (147, 43.0665) -> (115, 43.0665)
  line L22 (120.6, 5.8665) -> (120.6, 3.8665)
  line L23 (115, -0.0335) -> (147, -0.0335)
  line L24 (120.6, 3.8665) -> (141.4, 3.8665)
  line L25 (115, 43.0665) -> (115, -0.0335)
  line L26 (116.8, 42.0665) -> (116.8, 43.0665)
  line L27 (145.2, 43.0665) -> (145.2, 42.0665)
  line L28 (122.6, 5.8665) -> (121.6, 5.8665)
  line L29 (122.6, 5.8665) -> (120.6, 5.8665)
  line L30 (147, -0.0335) -> (147, 43.0665)
  line L31 (145.2, 42.0665) -> (116.8, 42.0665)
  line L32 (138, 4.8665) -> (134, 4.8665)
  line L33 (134, 3.8665) -> (138, 3.8665)
  line L34 (121.6, 4.8665) -> (122.6, 4.8665)
  line L35 (116.8, 43.0665) -> (145.2, 43.0665)
  line L36 (120.6, 3.8665) -> (122.6, 3.8665)
  line L37 (117.1, 39.0665) -> (119.1, 39.0665)
  line L38 (119.1, 39.0665) -> (119.1, 37.0665)
  line L39 (119.1, 37.0665) -> (117.1, 37.0665)
  line L40 (117.1, 37.0665) -> (117.1, 39.0665)
  line L41 (119.1, 37.0665) -> (118.1, 37.0665)
  line L42 (118.1, 37.0665) -> (118.1, 38.0665)
  line L43 (118.1, 38.0665) -> (119.1, 38.0665)
  line L44 (119.1, 38.0665) -> (119.1, 37.0665)
  line L45 (142.9, 39.0665) -> (144.9, 39.0665)
  line L46 (144.9, 39.0665) -> (144.9, 37.0665)
  line L47 (144.9, 37.0665) -> (142.9, 37.0665)
  line L48 (142.9, 37.0665) -> (142.9, 39.0665)
  line L49 (142.9, 37.0665) -> (143.9, 37.0665)
  line L50 (143.9, 37.0665) -> (143.9, 38.0665)
  line L51 (143.9, 38.0665) -> (142.9, 38.0665)
  line L52 (142.9, 38.0665) -> (142.9, 37.0665)
  line L53 (131, 12.9665) -> (131, 42.0665) construction
  line L54 (128, 39.0665) -> (122, 39.0665)
  line L55 (122, 39.0665) -> (122, 38.0665)
  line L56 (122, 38.0665) -> (128, 38.0665)
  line L57 (128, 38.0665) -> (128, 39.0665)
  line L58 (134, 38.0665) -> (140, 38.0665)
  line L59 (140, 38.0665) -> (140, 39.0665)
  line L60 (140, 39.0665) -> (134, 39.0665)
  line L61 (134, 39.0665) -> (134, 38.0665)
  line L62 (118.1, 28.9665) -> (119.1, 28.9665)
  line L63 (119.1, 28.9665) -> (119.1, 22.9665)
  line L64 (119.1, 22.9665) -> (118.1, 22.9665)
  line L65 (118.1, 22.9665) -> (118.1, 28.9665)
  line L66 (142.9, 22.9665) -> (143.9, 22.9665)
  line L67 (143.9, 22.9665) -> (143.9, 28.9665)
  line L68 (143.9, 28.9665) -> (142.9, 28.9665)
  line L69 (142.9, 28.9665) -> (142.9, 22.9665)
  line L70 (115, 4.9665) -> (116, 4.9665)
  line L71 (116, 4.9665) -> (116, 16.9665)
  line L72 (116, 16.9665) -> (115, 16.9665)
  line L73 (115, 16.9665) -> (115, 4.9665)
  line L74 (147, 4.9665) -> (146, 4.9665)
  line L75 (146, 4.9665) -> (146, 16.9665)
  line L76 (146, 16.9665) -> (147, 16.9665)
  line L77 (147, 16.9665) -> (147, 4.9665)
  line L78 (128, 19.9665) -> (134, 19.9665)
  line L79 (134, 19.9665) -> (134, 17.9665)
  line L80 (134, 17.9665) -> (128, 17.9665)
  line L81 (128, 17.9665) -> (128, 19.9665)
  circle A2 centre (116.6, 29.9665) radius 1
  circle A3 centre (145.4, 29.9665) radius 1
  dimension "d210" = 32
  dimension "d211" = 43.1
  dimension "d212" = 2.2
  dimension "d213" = 2
  dimension "d214" = 2
  dimension "d215" = 2.2
  dimension "d216" = 2
  dimension "d217" = 2
  dimension "d224" = 20.8
  dimension "d225" = 9.1
  dimension "d226" = 3.9
  dimension "d227" = 5.6
  dimension "d251" = 2
  dimension "d252" = 2
  dimension "d253" = 1
  dimension "d254" = 1
  dimension "d255" = 2
  dimension "d256" = 2
  dimension "d257" = 1
  dimension "d258" = 1
  dimension "d267" = 4
  dimension "d268" = 1
  dimension "d269" = 3
  dimension "d270" = 4
  dimension "d271" = 1
  dimension "d272" = 3
  dimension "d274" = 28.4
  dimension "d275" = 1
  dimension "d276" = 1.8
  dimension "d306" = 2
  dimension "d307" = 2
  dimension "d308" = 2.1
  dimension "d309" = 4
  dimension "d310" = 1
  dimension "d311" = 1
  dimension "d312" = 2
  dimension "d313" = 2
  dimension "d314" = 2.1
  dimension "d315" = 4
  dimension "d316" = 1
  dimension "d317" = 1
  dimension "d320" = 6
  dimension "d321" = 1
  dimension "d322" = 3
  dimension "d323" = 6
  dimension "d324" = 1
  dimension "d325" = 3
  dimension "d326" = 4
  dimension "d327" = 4
  dimension "d332" = 1
  dimension "d333" = 6
  dimension "d334" = 3.1
  dimension "d335" = 23
  dimension "d336" = 1
  dimension "d337" = 6
  dimension "d338" = 3.1
  dimension "d339" = 23
  dimension "d380" = 1
  dimension "d381" = 12
  dimension "d382" = 5
  dimension "d383" = 1
  dimension "d384" = 12
  dimension "d385" = 5
  dimension "d396" = 6
  dimension "d397" = 2
  dimension "d398" = 18
  dimension "d399" = 13
  dimension "d444" = 2
  dimension "d445" = 1.6
  dimension "d446" = 30
  dimension "d447" = 2
  dimension "d448" = 1.6
  dimension "d449" = 30
  constraint horizontal L23
  constraint vertical L30
  constraint horizontal L21
  constraint vertical L25
  constraint horizontal L24
  constraint vertical L2
  constraint horizontal L19
  constraint vertical L4
  constraint horizontal L36
  constraint vertical L0
  constraint horizontal L29
  constraint vertical L22
  constraint horizontal L28
  constraint vertical L20
  constraint horizontal L34
  constraint vertical L18
  constraint horizontal L12
  constraint vertical L8
  constraint horizontal L7
  constraint vertical L16
  constraint horizontal L11
  constraint vertical L14
  constraint horizontal L3
  constraint vertical L1
  constraint horizontal L10
  constraint vertical L17
  constraint horizontal L15
  constraint vertical L13
  constraint coincident L10.start L24
  constraint midpoint L6.start L24
  constraint midpoint L6.end L19
  constraint horizontal L33
  constraint vertical L9
  constraint horizontal L32
  constraint vertical L5
  constraint coincident L5.end L24
  constraint horizontal L35
  constraint vertical L27
  constraint horizontal L31
  constraint vertical L26
  constraint coincident L26.end L21
  constraint horizontal L37
  constraint vertical L38
  constraint horizontal L39
  constraint vertical L40
  constraint horizontal L41
  constraint vertical L42
  constraint horizontal L43
  constraint vertical L44
  constraint horizontal L45
  constraint vertical L46
  constraint horizontal L47
  constraint vertical L48
  constraint horizontal L49
  constraint vertical L50
  constraint horizontal L51
  constraint vertical L52
  constraint midpoint L31 L53.end
  constraint horizontal L54
  constraint vertical L55
  constraint horizontal L56
  constraint vertical L57
  constraint horizontal L58
  constraint vertical L59
  constraint horizontal L60
  constraint vertical L61
  constraint horizontal L62
  constraint vertical L63
  constraint horizontal L64
  constraint vertical L65
  constraint horizontal L66
  constraint vertical L67
  constraint horizontal L68
  constraint vertical L69
  constraint horizontal L70
  constraint vertical L71
  constraint horizontal L72
  constraint vertical L73
  constraint coincident L25 L70.start
  constraint horizontal L74
  constraint vertical L75
  constraint horizontal L76
  constraint vertical L77
  constraint coincident L30 L74.start
  constraint horizontal L78
  constraint vertical L79
  constraint horizontal L80
  constraint vertical L81
  measures "d210" distance of L23.end L23.start
  measures "d211" distance of L23.start L21.end
  measures "d212" diameter of A1
  measures "d213" distance of A1.centre L23
  measures "d214" distance of A1.centre L25
  measures "d215" diameter of A0
  measures "d216" distance of A0.centre L23
  measures "d217" distance of A0.centre L30
  measures "d224" distance of L4.end L2.start
  measures "d225" distance of L4.end L4.start
  measures "d226" distance of L23 L24
  measures "d227" distance of L4 L25
  measures "d251" distance of L4.end L0.start
  measures "d252" distance of L4.end L22.start
  measures "d253" distance of L0.end L20.start
  measures "d254" distance of L0.end L18.start
  measures "d255" distance of L8.start L2.start
  measures "d256" distance of L7.end L2.start
  measures "d257" distance of L11.end L1.end
  measures "d258" distance of L1.end L1.start
  measures "d267" distance of L10.start L10.end
  measures "d268" distance of L10.start L13.start
  measures "d269" distance of L6 L17
  measures "d270" distance of L5.end L9.start
  measures "d271" distance of L5.end L5.start
  measures "d272" distance of L5 L6
  measures "d274" distance of L27.start L26.end
  measures "d275" distance of L26.start L26.end
  measures "d276" distance of L25 L26
  measures "d306" distance of L37.start L37.end
  measures "d307" distance of L37.start L39.end
  measures "d308" distance of L25 L40
  measures "d309" distance of L21 L37
  measures "d310" distance of L38.end L41.end
  measures "d311" distance of L38.end L43.end
  measures "d312" distance of L45.start L45.end
  measures "d313" distance of L45.start L47.end
  measures "d314" distance of L30 L46
  measures "d315" distance of L35 L45
  measures "d316" distance of L47.end L49.end
  measures "d317" distance of L47.end L51.end
  measures "d320" distance of L54.start L54.end
  measures "d321" distance of L54.start L56.end
  measures "d322" distance of L53 L57
  measures "d323" distance of L58.start L58.end
  measures "d324" distance of L58.start L60.end
  measures "d325" distance of L53 L61
  measures "d326" distance of L21 L54
  measures "d327" distance of L35 L60
  measures "d332" distance of L62.start L62.end
  measures "d333" distance of L62.start L64.end
  measures "d334" distance of L25 L65
  measures "d335" distance of L23 L64
  measures "d336" distance of L66.start L66.end
  measures "d337" distance of L66.start L68.end
  measures "d338" distance of L30 L67
  measures "d339" distance of L23 L66
  measures "d380" distance of L70.start L70.end
  measures "d381" distance of L70.start L72.end
  measures "d382" distance of L23 L70
  measures "d383" distance of L74.start L74.end
  measures "d384" distance of L74.start L76.end
  measures "d385" distance of L23 L74
  measures "d396" distance of L78.start L78.end
  measures "d397" distance of L78.start L80.end
  measures "d398" distance of L23 L80
  measures "d399" distance of L25 L81
  measures "d444" diameter of A2
  measures "d445" distance of L25 A2.centre
  measures "d446" distance of L23 A2.centre
  measures "d447" diameter of A3
  measures "d448" distance of L30 A3.centre
  measures "d449" distance of L23 A3.centre
extrude "Extrude31" add sketch "Side" along normal blind 1 separate body contours L0 L4 L20 L22 L24 L29 L34 L36 | L0 L1 L2 L4 L5 L7 L8 L9 L11 L13 L15 L17 L18 L19 L24 L28 L29 L32 | L0 L18 L20 L28 L29 L34 | L10 L13 L15 L17 L24 | L5 L9 L24 L32 L33 | L2 L3 L7 L8 L12 L14 L16 L24 | L1 L3 L7 L8 L11 L14 | L21 L23 L25 L26 L27 L30 L31 L70 L71 L72 L74 L75 L76 | L21 L26 L27 L31 L35 | L30 L74 L75 L76 L77 | L25 L70 L71 L72 L73 | L37 L38 L39 L40 L42 L43 | L38 L39 L41 L42 L43 L44 | L45 L46 L47 L48 L50 L51 | L47 L48 L49 L50 L51 L52 | L54 L55 L56 L57 | L58 L59 L60 L61 | L62 L63 L64 L65 | L66 L67 L68 L69 | L78 L79 L80 L81 | A2 | A3 makes body 6
extrude "Extrude32" add sketch "Side" along normal blind 4 contours L0 L4 L20 L22 L24 L29 L34 L36 | L10 L13 L15 L17 L24 | L5 L9 L24 L32 L33 | L2 L3 L7 L8 L12 L14 L16 L24 bodies 6
extrude "Extrude33" add sketch "Side" along normal blind 2 contours L21 L26 L27 L31 L35 bodies 6
fillet "Fillet6" radius 0.4 4 edges at (147, 0.5, 0.0335) (115, 0.5, 0.0335) (115, 0.5, -43.0665) (147, 0.5, -43.0665) on bodies 6
fillet "Fillet7" radius 0.4 2 edges at (126, 1, -4.8665) (136, 1, -4.8665) on bodies 6
extrude "Extrude34" add sketch "Side" along normal blind 4 contours L37 L38 L39 L40 L42 L43 | L45 L46 L47 L48 L50 L51 bodies 6
extrude "Extrude35" add sketch "Side" along normal blind 4 contours L54 L55 L56 L57 | L58 L59 L60 L61 bodies 6
fillet "Fillet8" radius 0.4 2 edges at (137, 1, -38.0665) (125, 1, -38.0665) on bodies 6
extrude "Extrude36" add sketch "Side" along normal blind 4 contours L62 L63 L64 L65 | L66 L67 L68 L69 bodies 6
fillet "Fillet9" radius 0.4 2 edges at (119.1, 1, -25.9665) (142.9, 1, -25.9665) on bodies 6
extrude "Extrude37" add sketch "Side IO" along normal blind 4 contours L78 L79 L80 L81 | L82 L83 L84 L85 bodies 2
fillet "Fillet10" radius 0.4 2 edges at (55, 1, -38.1196) (67, 1, -38.1196) on bodies 2
sketch "Frame Decor-v1 L" plane through (0, 0, 0) normal (-1, 0, 0) x (0, 0, 1)
  line L0 (-43.1, 0) -> (0, 0)
  line L1 (0, 0) -> (0, 60)
  line L2 (0, 60) -> (-43.1, 60)
  line L3 (-43.1, 60) -> (-43.1, 0)
  line L4 (-5, 0) -> (-9, 0)
  line L5 (-17, 60) -> (-5, 60)
  line L6 (-5, 60) -> (-5, 0)
  line L7 (-9, 0) -> (-9, 45)
  arc A0 (-9, 45) -> (-17, 60) centre (-27.0625, 45) ccw
  point P0 (-9, 45)
  dimension "d359" = 4
  dimension "d360" = 60
  dimension "d361" = 5
  constraint horizontal L4
  constraint horizontal L5
  constraint vertical L6
  constraint coincident L0 L4.start
  constraint coincident P0 L7.end
  constraint perpendicular L4 L7
  constraint tangent L7 A0
  measures "d359" distance of L4.start L4.end
  measures "d360" distance of L4.start L5.end
  measures "d361" distance of L1 L6
extrude "Extrude38" cut sketch "Frame Decor-v1 L" against normal blind 1 contours L0 L2 L4 L5 L6 L7 A0 bodies 1
sketch "Frame Decor-v1 R" plane through (32, 0, 0) normal (1, 0, 0) x (0, 0, -1)
  line L0 (0, 0) -> (43.1, 0)
  line L1 (43.1, 0) -> (43.1, 60)
  line L2 (43.1, 60) -> (0, 60)
  line L3 (0, 60) -> (0, 0)
  line L4 (0, 0) -> (43, 0)
  line L5 (0, 60) -> (0, 0)
  line L6 (43, 0) -> (43, 60)
  line L7 (43, 60) -> (0, 60)
  line L8 (5, 0) -> (9, 0)
  line L9 (17, 60) -> (5, 60)
  line L10 (5, 60) -> (5, 0)
  line L11 (9, 0) -> (9, 45)
  arc A0 (17, 60) -> (9, 45) centre (27.0625, 45) ccw
  point P0 (43, 0)
  point P1 (9, 45)
  dimension "d367" = 4
  dimension "d368" = 60
  dimension "d369" = 5
  constraint horizontal L8
  constraint horizontal L9
  constraint vertical L10
  constraint coincident L4 L8.start
  constraint coincident L7 L9.start
  constraint coincident L2 L9.start
  constraint parallel L7 L9
  constraint coincident P1 L11.end
  constraint tangent L11 A0
  measures "d367" distance of L8.start L8.end
  measures "d368" distance of L8.start L9.end
  measures "d369" distance of L5 L10
extrude "Extrude39" cut sketch "Frame Decor-v1 R" against normal blind 1 contours L0 L2 L4 L7 L8 L9 L10 L11 A0 bodies 1
extrude "Extrude40" cut sketch "Side IO" along normal blind 1 contours L3 L86 L87 L88 L89 | L1 L90 L91 L92 L93 bodies 2
extrude "Extrude41" cut sketch "Side" along normal blind 1 contours L30 L74 L75 L76 L77 | L25 L70 L71 L72 L73 bodies 6